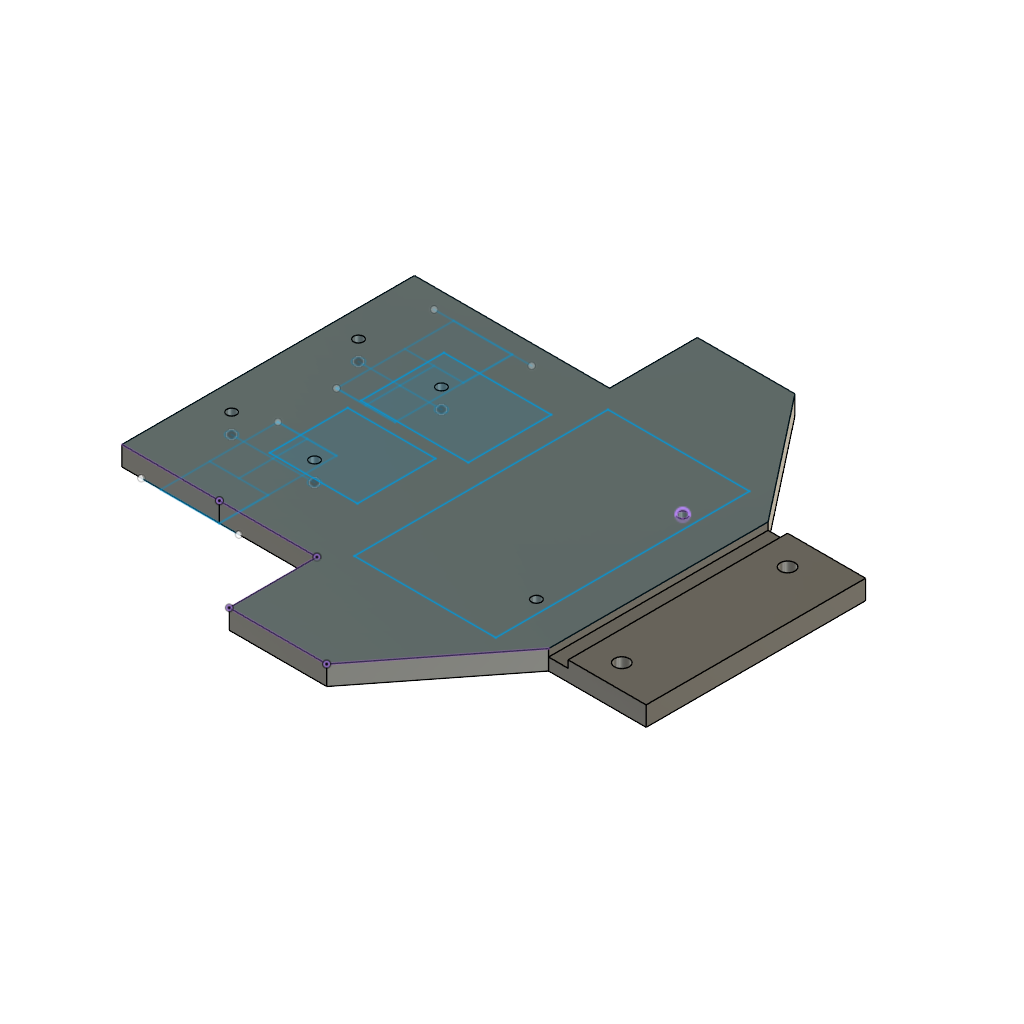
robot (Autodesk Fusion 360 design; units mm, degrees)
Autodesk Fusion 360 part; units mm, degrees
sketch "Sketch1" plane through (0, 0, 0) normal (0, 0, 1) x (1, 0, 0)
  line L0 (0, 0) -> (0, 45)
  line L1 (0, 45) -> (-20, 45)
  line L2 (0, 0) -> (-20, 0)
  line L3 (-20, 45) -> (-20, 0)
  circle A0 centre (-10, 5) radius 1.5
  circle A1 centre (-10, 39) radius 1.5
  line L4 (-80, 52.5) -> (-60, 52.5)
  line L5 (-60, 52.5) -> (-60, 70.5)
  line L6 (-60, 70.5) -> (-40, 70.5)
  line L7 (-40, 70.5) -> (-20, 45)
  line L8 (-100, 22.5) -> (-100, -7.5024)
  line L9 (-100, 22.5) -> (-100, -7.5024)
  line L10 (-80, -7.5024) -> (-80, -7.5)
  line L11 (-80, -7.5) -> (-60, -7.5)
  line L12 (-60, -7.5) -> (-60, -25.5)
  line L13 (-60, -25.5) -> (-40, -25.5)
  line L14 (-40, -25.5) -> (-20, 0)
  line L15 (-80, 52.5) -> (-100, 52.5)
  line L16 (-100, 52.5) -> (-100, 22.5)
  line L17 (-100, -7.5024) -> (-60, -7.5)
  line L18 (-20, 22.5) -> (-30, 22.5)
  line L19 (-30, 22.5) -> (-30, 37.5)
  circle A2 centre (-30, 7.5) radius 1
  circle A3 centre (-30, 37.5) radius 1
  dimension "d1" = 45
  dimension "d3" = 20
  dimension "d9" = 3
  dimension "d10" = 3
  dimension "d16" = 20
  dimension "d17" = 18
  dimension "d18" = 20
  dimension "d60" = 15
  dimension "d61" = 15
  dimension "d62" = 2
  dimension "d63" = 2
  constraint coincident L0.start L2.start
  constraint vertical L0
  constraint perpendicular L0 L1
  constraint perpendicular L0 L2
  constraint perpendicular L4 L5
  constraint perpendicular L5 L6
  constraint perpendicular L15 L16
  constraint midpoint L3 L18.start
  constraint perpendicular L3 L18
  constraint perpendicular L18 L19
  constraint coincident L19.end A3.centre
  measures "d1" distance of L0.start L0.end
  measures "d3" distance of L0.start L2.end
  measures "d9" diameter of A0
  measures "d10" diameter of A1
  measures "d16" distance of L4.start L4.end
  measures "d17" distance of L4.end L5.end
  measures "d18" distance of L5.end L6.end
  measures "d60" distance of L18.end A2.centre
  measures "d61" distance of L18.end L19.end
  measures "d62" diameter of A2
  measures "d63" diameter of A3
extrude "Extrude1" add sketch "Sketch1" along normal blind 4 contours L3 L4 L5 L6 L7 L8 L9 L11 L12 L13 L14 L15 L16 L17 | A2 makes body 1
extrude "Extrude2" add sketch "Sketch1" along normal blind 3 contours L0 L1 L2 L3 bodies 1
sketch "esp32" plane through (0, 0, 4) normal (0, 0, 1) x (-1, 0, 0)
  line L0 (100, -52.5) -> (100, 7.5024)
  line L1 (20, 0) -> (20, -45)
  line L2 (20, -45) -> (40, -70.5)
  line L3 (40, -70.5) -> (60, -70.5)
  line L4 (60, -70.5) -> (60, -52.5)
  line L5 (60, -52.5) -> (100, -52.5)
  line L6 (56.323, -22.5) -> (56.323, -48.5)
  line L7 (56.323, -22.5) -> (56.323, 3.5)
  line L8 (56.323, 3.5) -> (27.323, 3.5)
  line L9 (27.323, 3.5) -> (27.323, -48.5)
  line L10 (27.323, -48.5) -> (56.323, -48.5)
  line L11 (80, 7.5012) -> (80, 7.5)
  line L12 (80, 7.5) -> (60, 7.5)
  line L13 (60, 7.5) -> (60, 25.5)
  line L14 (60, 25.5) -> (40, 25.5)
  line L15 (40, 25.5) -> (20, 0)
  line L16 (100, 7.5024) -> (80, 7.5012)
  circle A0 centre (30, -37.5) radius 1
  dimension "d26" = 26
  dimension "d27" = 26
  dimension "d28" = 29
  dimension "d29" = 52
  constraint perpendicular L7 L8
  measures "d26" distance of L6.start L6.end
  measures "d27" distance of L6.start L7.end
  measures "d28" distance of L7.end L8.end
  measures "d29" distance of L8.end L9.end
sketch "hbrug, buck" plane through (0, 0, 4) normal (0, 0, 1) x (-1, 0, 0)
  line L0 (65.3163, -6.1321) -> (83.3163, -6.1321)
  line L1 (83.3163, -6.1321) -> (83.3163, -22.1321)
  line L2 (83.3163, -22.1321) -> (65.3163, -22.1321)
  line L3 (65.3163, -22.1321) -> (65.3163, -6.1321)
  line L4 (83.2387, -24.7796) -> (61.2387, -24.7796)
  line L5 (61.2387, -24.7796) -> (61.2387, -41.7796)
  line L6 (61.2387, -41.7796) -> (83.2387, -41.7796)
  line L7 (83.2387, -41.7796) -> (83.2387, -24.7796)
  dimension "d30" = 18
  dimension "d31" = 16
  dimension "d32" = 22
  dimension "d33" = 17
  constraint horizontal L0
  constraint vertical L1
  constraint horizontal L2
  constraint vertical L3
  constraint horizontal L4
  constraint vertical L5
  constraint horizontal L6
  constraint vertical L7
  measures "d30" distance of L0.start L0.end
  measures "d31" distance of L0.start L2.end
  measures "d32" distance of L4.start L4.end
  measures "d33" distance of L4.start L6.end
sketch "Sketch4" plane through (0, 0, 0) normal (0, 0, 1) x (1, 0, 0)
sketch "Sketch5" plane through (0, 0, 0) normal (0, 0, 1) x (1, 0, 0)
  line L0 (-75.9891, -7.5055) -> (-95.9891, -7.5055)
  line L1 (-85.9891, 2.4945) -> (-85.9891, 16.4945)
  line L2 (-75.9431, 52.4707) -> (-95.9431, 52.4707)
  line L3 (-85.9431, 42.4707) -> (-85.9431, 28.4707)
  line L4 (-85.9431, 28.4707) -> (-79.9431, 28.4707)
  line L5 (-85.9431, 28.4707) -> (-91.9431, 28.4707)
  line L6 (-79.9431, 28.4707) -> (-91.9431, 28.4707)
  line L7 (-91.9431, 28.4707) -> (-91.9431, 52.4707)
  line L8 (-91.9431, 52.4707) -> (-79.9431, 52.4707)
  line L9 (-79.9431, 52.4707) -> (-79.9431, 28.4707)
  line L10 (-85.9891, 16.4945) -> (-79.9891, 16.4945)
  line L11 (-85.9891, 16.4945) -> (-91.9891, 16.4945)
  line L12 (-79.9891, 16.4945) -> (-91.9891, 16.4945)
  line L13 (-91.9891, 16.4945) -> (-91.9891, -7.5055)
  line L14 (-91.9891, -7.5055) -> (-79.9891, -7.5055)
  line L15 (-79.9891, -7.5055) -> (-79.9891, 16.4945)
  line L16 (-79.9891, -7.5055) -> (-79.9891, 2.4945)
  line L17 (-79.9891, 2.4945) -> (-91.9891, 2.4945)
  line L18 (-79.9431, 52.4707) -> (-79.9431, 42.4707)
  line L19 (-79.9431, 42.4707) -> (-91.9431, 42.4707)
  line L20 (-85.9891, 9.4945) -> (-77.4891, 9.4945)
  line L21 (-85.9891, 9.4945) -> (-94.4891, 9.4945)
  circle A0 centre (-94.4891, 9.4945) radius 1
  circle A1 centre (-77.4891, 9.4945) radius 1
  line L22 (-85.9431, 35.4707) -> (-77.4431, 35.4707)
  line L23 (-85.9431, 35.4707) -> (-94.4431, 35.4707)
  circle A2 centre (-77.4431, 35.4707) radius 1
  circle A3 centre (-94.4431, 35.4707) radius 1
  dimension "d37" = 20
  dimension "d39" = 20
  dimension "d41" = 6
  dimension "d42" = 6
  dimension "d43" = 12
  dimension "d44" = 6
  dimension "d45" = 6
  dimension "d46" = 12
  dimension "d47" = 10
  dimension "d48" = 10
  dimension "d49" = 8.5
  dimension "d50" = 8.5
  dimension "d51" = 2
  dimension "d52" = 2
  dimension "d53" = 8.5
  dimension "d54" = 8.5
  dimension "d55" = 2
  dimension "d56" = 2
  constraint horizontal L0
  constraint perpendicular L0 L1
  constraint horizontal L2
  constraint perpendicular L2 L3
  constraint perpendicular L3 L4
  constraint perpendicular L3 L5
  constraint horizontal L6
  constraint vertical L7
  constraint horizontal L8
  constraint vertical L9
  constraint perpendicular L1 L10
  constraint perpendicular L1 L11
  constraint horizontal L12
  constraint vertical L13
  constraint horizontal L14
  constraint vertical L15
  constraint perpendicular L14 L16
  constraint coincident L13 L17.end
  constraint perpendicular L13 L17
  constraint coincident L17 L1.start
  constraint perpendicular L8 L18
  constraint coincident L7 L19.end
  constraint perpendicular L7 L19
  constraint coincident L19 L3.start
  constraint midpoint L1 L20.start
  constraint perpendicular L15 L20
  constraint perpendicular L13 L21
  constraint coincident L21.end A0.centre
  constraint coincident L20.end A1.centre
  constraint midpoint L3 L22.start
  constraint perpendicular L3 L22
  constraint perpendicular L3 L23
  constraint coincident L22.end A2.centre
  constraint coincident L23.end A3.centre
  measures "d37" distance of L0.start L0.end
  measures "d39" distance of L2.start L2.end
  measures "d41" distance of L3.end L4.end
  measures "d42" distance of L3.end L5.end
  measures "d43" distance of L4.end L5.end
  measures "d44" distance of L1.end L10.end
  measures "d45" distance of L1.end L11.end
  measures "d46" distance of L10.end L11.end
  measures "d47" distance of L14.end L16.end
  measures "d48" distance of L8.end L18.end
  measures "d49" distance of L20.start L20.end
  measures "d50" distance of L20.start L21.end
  measures "d51" diameter of A0
  measures "d52" diameter of A1
  measures "d53" distance of L22.start L22.end
  measures "d54" distance of L22.start L23.end
  measures "d55" diameter of A2
  measures "d56" diameter of A3
extrude "Extrude3" cut sketch "Sketch5" along normal blind 4 contours A0 | A1 | A2 | A3 bodies 1
sketch "Sketch6" plane through (0, 0, 4) normal (0, 0, 1) x (-1, 0, 0)
extrude "Extrude4" add sketch "Sketch1" along normal blind 11 separate body contours A2 | A3 makes body 2 at (-29.0012, 7.4502, 7.3333) makes body 3 at (-30.9397, 37.158, 7.3333)
extrude "Extrude5" cut 2 faces at (-30.171, 7.8177, 11) (-29.6849, 37.7429, 11) along direction (0, 0, -1) blind 11 on bodies 2 3 bodies 1 2 3
sketch "Sketch7" plane through (0, 0, 3) normal (0, 0, 1) x (-1, 0, 0)
  circle A0 centre (10, -5) radius 1.5
  circle A1 centre (10, -39) radius 1.5
  line L0 (0, 0) -> (0, -45)
  line L1 (0, -45) -> (20, -45)
  line L2 (20, -45) -> (20, 0)
  line L3 (20, 0) -> (0, 0)
sketch "Sketch8" plane through (0, 45, 0) normal (0, 1, 0) x (-1, 0, 0)
  line L0 (0, 0) -> (20, 0)
  line L1 (20, 0) -> (20, 3)
  line L2 (20, 3) -> (0, 3)
  line L3 (0, 3) -> (0, 0)
  line L4 (20, 3) -> (20, 2.5)
  line L5 (20, 2.5) -> (22.3707, 5.4299)
  line L6 (20, 2.5) -> (16, 2.5)
  line L7 (20, 3) -> (16, 3)
  line L8 (16, 3) -> (16, 2.5)
  dimension "d68" = 0.5
  dimension "d69" = 4
  dimension "d70" = 4
  constraint coincident L1.end L2.start
  constraint perpendicular L2 L4
  constraint perpendicular L4 L6
  constraint perpendicular L1 L7
  measures "d68" distance of L1.end L4.end
  measures "d69" distance of L4.end L6.end
  measures "d70" distance of L1.end L7.end
extrude "Extrude6" cut sketch "Sketch8" against normal blind 48 contours L1 L2 L4 L6 L7 L8 bodies 1
extrude "Extrude7" add 1 faces at (-2.9668, 27.6599, 3) along direction (0, 0, 1) blind 1 on bodies 1 bodies 1 2 3
